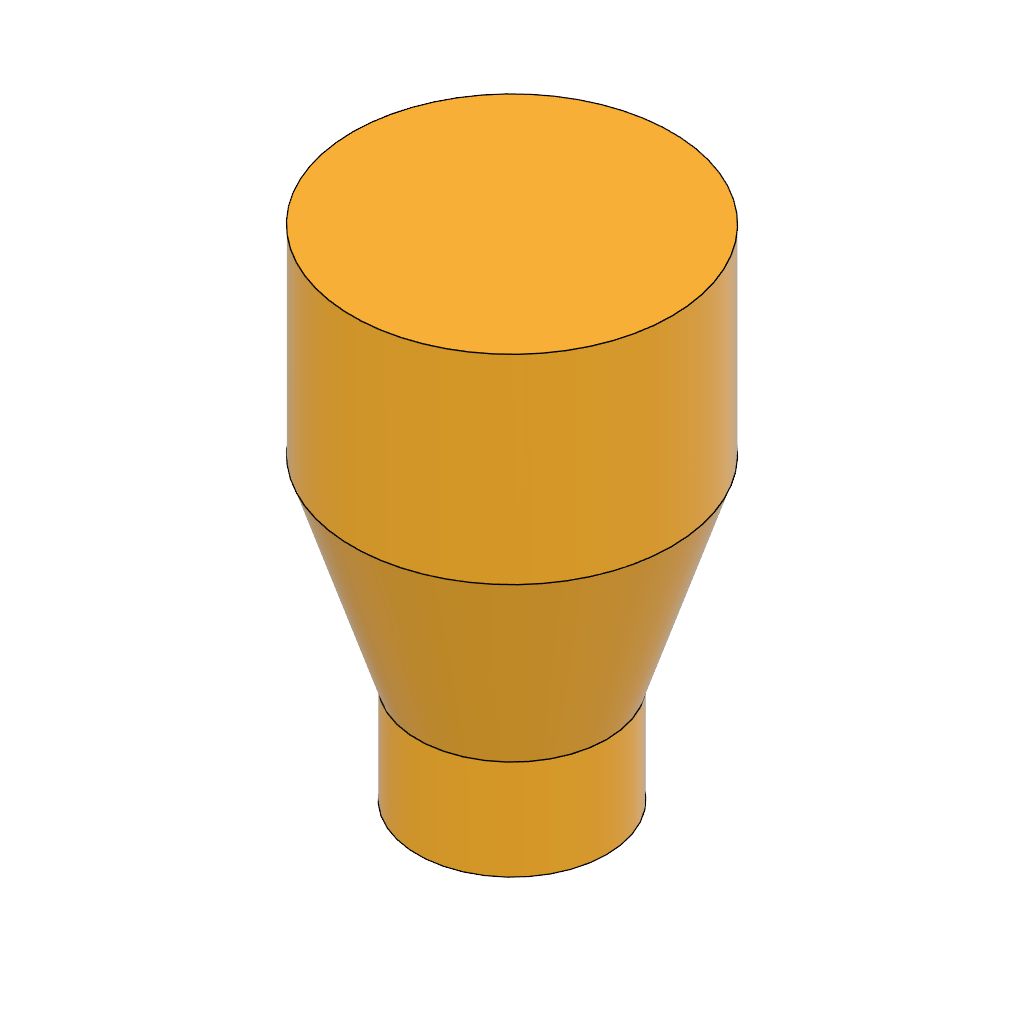
ProbingTip (Autodesk Fusion 360 design; units mm, degrees)
Autodesk Fusion 360 part; units mm, degrees
cylinder "CylinderPrimitive1" add diameter 8 height 5 placed x (1, 0, 0) y (0, 0, -1) z (0, 1, 0) at (0, 0, 0) makes body 1
ref_plane "WorkPlane1" through (0, -5, 0) normal (0, -1, 0) x (-1, 0, 0)
cylinder "CylinderPrimitive2" add diameter 4.75 height 2.5 placed x (1, 0, 0) y (0, 0, 1) z (0, -1, 0) at (0, -5, 0) separate body makes body 2
loft "Loft1" add section 1 face at (0.0821, -5, 0.5322) section 2 face at (-1.2456, 0, -0.0132) on bodies 1 2 bodies 1 2
ref_plane "WorkPlane2" through (0, -20, 0) normal (0, -1, 0) x (1, 0, 0)
